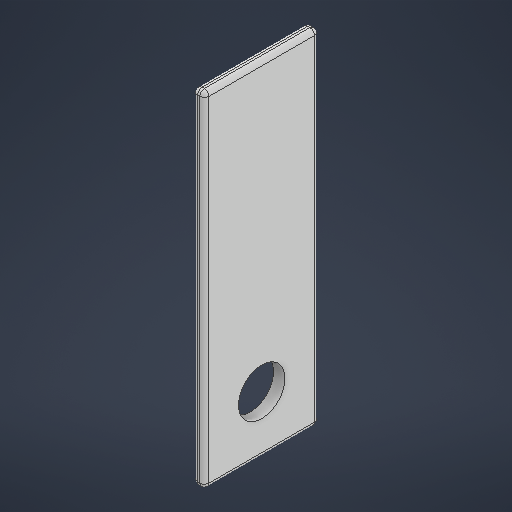
# Autodesk Inventor part: muslo
Saved by Autodesk Inventor 2027.1 (Build 311270010, 270A)
## iProperties
Created: 2026-11-19
Part Number: muslo
Material: Generic
Document SubType Name: Modeling
Designer: ASUS
Density: 1 g/cm^3
Appearance: Default
Author: ASUS
Autodesk Inventor part; units mm, degrees
ref_plane "YZ Plane" through (0, 0, 0) normal (1, 0, 0) x (0, 1, 0)
ref_plane "XZ Plane" through (0, 0, 0) normal (0, 1, 0) x (-1, 0, 0)
ref_plane "XY Plane" through (0, 0, 0) normal (0, 0, 1) x (1, 0, 0)
sketch "Sketch1" plane through (0, 0, 0) normal (1, 0, 0) x (0, 1, 0)
  circle A0 centre (-17.7516, -3.8337) radius 10.15
  line L0 (-42.7516, -28.8337) -> (107.2484, -28.8337)
  line L1 (107.2484, -28.8337) -> (107.2484, 21.1663)
  line L2 (107.2484, 21.1663) -> (-42.7516, 21.1663)
  line L3 (-42.7516, 21.1663) -> (-42.7516, -28.8337)
  point P0 (0, 0)
  point P1 (-21.7432, -13.1658)
  point P2 (-22.3283, 5.226)
  point P3 (-17.9299, 6.3148)
  point P4 (-13.7874, -13.1775)
  point P5 (-17.9299, -13.9821)
  point P6 (-42.7516, -3.8337)
  dimension "d1" = 20.3
  dimension "d12" = 150
  dimension "d13" = 25
  dimension "d14" = 50
  dimension "d15" = 25
  constraints: 8 end point, 5 point on circle, 2 parallel, 1 centre point, 1 horizontal, 1 midpoint, 1 perpendicular
  measures "d1" diameter of A0
  measures "d12" distance of L2.end L1.end
  measures "d13" distance from line of L0 A0.centre
  measures "d14" distance of L0.start L2.end
  measures "d15" distance of point (-42.752, -3.834) A0.centre
extrude "Extrusion1" add sketch "Sketch1" along normal blind 5
sketch "Sketch2" plane through (5, 0, 0) normal (1, 0, 0) x (0, 0, -1)
  circle A0 centre (0, -66.7379) radius 10
  circle A1 centre (0, -66.7379) radius 25
  point P0 (0, 0)
  dimension "d5" = 20
  dimension "d11" = 50
  constraints: 2 centre point, 1 coincident
  measures "d5" diameter of A0
  measures "d11" diameter of A1
extrude "Extrusion2" cut sketch "Sketch2" against normal blind 5 contours A0
fillet "Fillet4" radius 2 12 edges at (5, 107.2484, -3.8337) (0, 107.2484, -3.8337) (5, 32.2484, 21.1663) (0, 32.2484, 21.1663) (5, 32.2484, -28.8337) (2.5, 107.2484, -28.8337) (2.5, 107.2484, 21.1663) (0, 32.2484, -28.8337) (0, -42.7516, -3.8337) (5, -42.7516, -3.8337) (2.5, -42.7516, -28.8337) (2.5, -42.7516, 21.1663)
body "Solid1"
